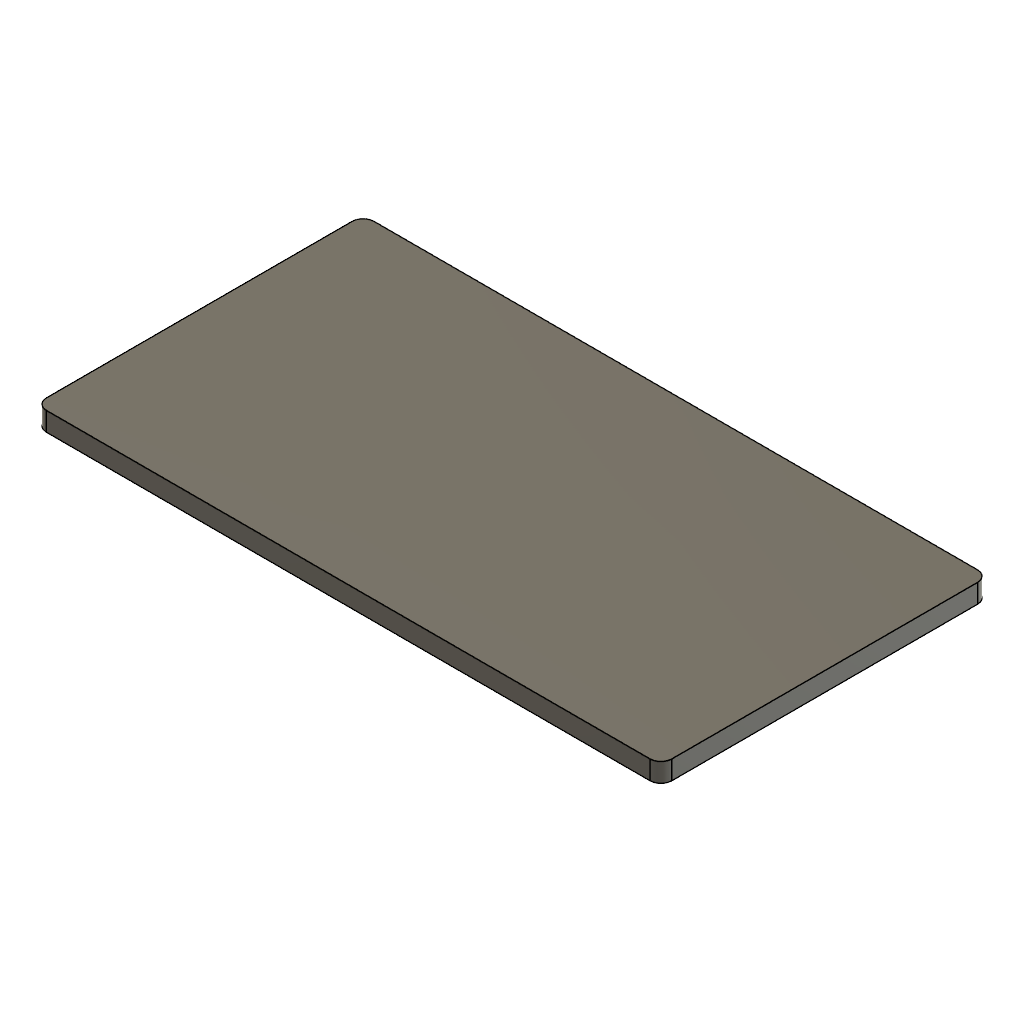
tapa_bateria (Autodesk Fusion 360 design; units mm, degrees)
part number: 2026-11-21-14-39-01-100
Autodesk Fusion 360 part; units mm, degrees
sketch "Sketch1" plane through (0, 0, 0) normal (0, 1, 0) x (1, 0, 0)
  line L0 (53.75, 26.25) -> (-53.75, 26.25)
  line L1 (-53.75, 26.25) -> (-53.75, -26.25)
  line L2 (-53.75, -26.25) -> (53.75, -26.25)
  line L3 (53.75, -26.25) -> (53.75, 26.25)
  line L4 (53.75, 26.25) -> (-53.75, -26.25) construction
  line L5 (-53.75, 26.25) -> (53.75, -26.25) construction
  line L6 (57.75, 30.25) -> (-57.75, 30.25)
  line L7 (-57.75, 30.25) -> (-57.75, -30.25)
  line L8 (-57.75, -30.25) -> (57.75, -30.25)
  line L9 (57.75, -30.25) -> (57.75, 30.25)
  dimension "d1" = 107.5
  dimension "d2" = 52.5
  dimension "d3" = 4
  constraint horizontal L0
  constraint perpendicular L0 L1
  constraint parallel L0 L2
  constraint parallel L1 L3
  constraint coincident L4 origin
  constraint coincident L5 origin
  measures "d1" distance of L1.end L2.end
  measures "d2" distance of L0.end L1.end
extrude "Extrude1" add sketch "Sketch1" along normal blind 30 contours L0 L1 L2 L3 | L6 L7 L8 L9 makes body 1
shell "Shell1" thickness 4 removed faces 1 at (-19.25, 30, 10.0833) on bodies 1
sketch "Sketch2" plane through (-57.75, 0, 0) normal (-1, 0, 0) x (0, 0, 1)
  line L0 (-30.25, 0) -> (30.25, 0)
  line L1 (30.25, 0) -> (30.25, 30)
  line L2 (30.25, 30) -> (-30.25, 30)
  line L3 (-30.25, 30) -> (-30.25, 0)
  line L4 (9, 17) -> (-9, 17)
  line L5 (-9, 17) -> (-9, 4)
  line L6 (-9, 4) -> (9, 4)
  line L7 (9, 4) -> (9, 17)
  line L8 (9, 17) -> (-9, 4) construction
  line L9 (-9, 17) -> (9, 4) construction
  point P0 (0, 10.5)
  dimension "d7" = 18
  dimension "d8" = 13
  dimension "d9" = 4
  constraint horizontal L4
  constraint perpendicular L4 L5
  constraint parallel L4 L6
  constraint parallel L5 L7
  constraint coincident L8 P0
  constraint coincident L9 P0
  measures "d7" distance of L5.end L6.end
  measures "d8" distance of L4.end L5.end
  measures "d9" distance of L0 L6
extrude "Extrude2" cut sketch "Sketch2" against normal blind 25 contours L4 L5 L6 L7 bodies 1
sketch "Sketch3" plane through (0, 0, 30.25) normal (0, 0, 1) x (1, 0, 0)
  line L0 (-57.75, 0) -> (57.75, 0)
  line L1 (57.75, 0) -> (57.75, 30)
  line L2 (57.75, 30) -> (-57.75, 30)
  line L3 (-57.75, 30) -> (-57.75, 0)
  line L4 (33.0622, 11) -> (50.0622, 11)
  line L5 (50.0622, 11) -> (50.0622, 4)
  line L6 (50.0622, 4) -> (33.0622, 4)
  line L7 (33.0622, 4) -> (33.0622, 11)
  dimension "d12" = 17
  dimension "d13" = 7
  dimension "d14" = 4
  constraint horizontal L4
  constraint vertical L5
  constraint horizontal L6
  constraint vertical L7
  measures "d12" distance of L4.start L4.end
  measures "d13" distance of L4.start L6.end
  measures "d14" distance of L0 L6
extrude "Extrude3" cut sketch "Sketch3" against normal blind 3 contours L4 L5 L6 L7 bodies 1
extrude "Extrude4" cut 1 faces at (44.3955, 6.3333, 27.25) along direction (0, 0, -1) blind 2 on bodies 1 bodies 1
sketch "Sketch4" plane through (0, 30, 0) normal (0, 1, 0) x (-1, 0, 0)
  line L0 (-53.75, 26.25) -> (53.75, 26.25)
  line L1 (53.75, 26.25) -> (53.75, -26.25)
  line L2 (53.75, -26.25) -> (-53.75, -26.25)
  line L3 (-53.75, -26.25) -> (-53.75, 26.25)
  line L4 (-57.75, 30.25) -> (-57.75, -30.25)
  line L5 (-57.75, -30.25) -> (57.75, -30.25)
  line L6 (57.75, -30.25) -> (57.75, 30.25)
  line L7 (57.75, 30.25) -> (-57.75, 30.25)
  line L8 (57.75, -30.25) -> (-57.75, -30.25)
  line L9 (-57.75, -30.25) -> (-57.75, 30.25)
  line L10 (-57.75, 30.25) -> (57.75, 30.25)
  line L11 (57.75, 30.25) -> (57.75, -30.25)
  constraint horizontal L8
  constraint vertical L9
  constraint horizontal L10
  constraint vertical L11
  constraint coincident L4.start L7.end
  constraint coincident L5.end L6.start
extrude "Extrude5" add sketch "Sketch4" along normal blind 2 bodies 1
sketch "Sketch5" plane through (0, 32, 0) normal (0, 1, 0) x (-1, 0, 0)
  line L0 (53.75, -26.25) -> (-53.75, -26.25)
  line L1 (-53.75, -26.25) -> (-53.75, 26.25)
  line L2 (-53.75, 26.25) -> (53.75, 26.25)
  line L3 (53.75, 26.25) -> (53.75, -26.25)
  line L4 (57.75, 30.25) -> (-57.75, 30.25)
  line L5 (-57.75, 30.25) -> (-57.75, -30.25)
  line L6 (-57.75, -30.25) -> (57.75, -30.25)
  line L7 (57.75, -30.25) -> (57.75, 30.25)
  line L8 (57.75, -30.25) -> (-57.75, -30.25)
  line L9 (-57.75, -30.25) -> (-57.75, 30.25)
  line L10 (-57.75, 30.25) -> (57.75, 30.25)
  line L11 (57.75, 30.25) -> (57.75, -30.25)
  constraint horizontal L8
  constraint vertical L9
  constraint horizontal L10
  constraint vertical L11
  constraint coincident L4.end L5.start
  constraint coincident L6.end L7.start
extrude "Extrude6" add sketch "Sketch5" along normal blind 3.5 separate body contours L0 L1 L2 L3 | L4 L5 L6 L7 L8 L9 L10 L11 makes body 2
sketch "Sketch6" plane through (0, 32, 0) normal (0, -1, 0) x (1, 0, 0)
  line L0 (57.75, 30.25) -> (-57.75, 30.25)
  line L1 (-57.75, 30.25) -> (-57.75, -30.25)
  line L2 (-57.75, -30.25) -> (57.75, -30.25)
  line L3 (57.75, -30.25) -> (57.75, 30.25)
  line L4 (-53.5, -26) -> (53.5, -26)
  line L5 (53.5, -26) -> (53.5, 26)
  line L6 (53.5, 26) -> (-53.5, 26)
  line L7 (-53.5, 26) -> (-53.5, -26)
  dimension "d23" = -4.25
extrude "Extrude7" add sketch "Sketch6" along normal blind 3.5 contours L4 L5 L6 L7 bodies 2
fillet "Fillet1" radius 2 8 edges at (57.75, 16, 30.25) (-57.75, 16, 30.25) (57.75, 16, -30.25) (-57.75, 16, -30.25) (57.75, 33.75, 30.25) (-57.75, 33.75, 30.25) (57.75, 33.75, -30.25) (-57.75, 33.75, -30.25) on bodies 1 2
fillet "Fillet2" radius 1 4 edges at (-55.75, 17, -9) (-55.75, 4, 9) (-55.75, 4, -9) (-55.75, 17, 9) on bodies 1
fillet "Fillet3" radius 0.5 4 edges at (50.0622, 11, 28.25) (50.0622, 4, 28.25) (33.0622, 4, 28.25) (33.0622, 11, 28.25) on bodies 1
sketch "Sketch7" plane through (0, 0, 30.25) normal (0, 0, 1) x (1, 0, 0)
  line L0 (50.0622, 10.5) -> (50.0622, 4.5)
  arc A0 (49.5622, 4) -> (50.0622, 4.5) centre (49.5622, 4.5) ccw
  line L1 (49.5622, 4) -> (33.5622, 4)
  arc A1 (33.0622, 4.5) -> (33.5622, 4) centre (33.5622, 4.5) ccw
  line L2 (33.0622, 4.5) -> (33.0622, 10.5)
  arc A2 (33.5622, 11) -> (33.0622, 10.5) centre (33.5622, 10.5) ccw
  line L3 (33.5622, 11) -> (49.5622, 11)
  arc A3 (50.0622, 10.5) -> (49.5622, 11) centre (49.5622, 10.5) ccw
  line L4 (-55.75, 32) -> (-55.75, 0)
  line L5 (-55.75, 0) -> (55.75, 0)
  line L6 (55.75, 0) -> (55.75, 32)
  line L7 (55.75, 32) -> (-55.75, 32)
  line L8 (-29.8148, 17) -> (-13.8148, 17)
  line L9 (-13.8148, 17) -> (-13.8148, 4)
  line L10 (-13.8148, 4) -> (-29.8148, 4)
  line L11 (-29.8148, 4) -> (-29.8148, 17)
  dimension "d32" = 16
  dimension "d33" = 13
  dimension "d34" = 4
  constraint horizontal L8
  constraint vertical L9
  constraint horizontal L10
  constraint vertical L11
  measures "d32" distance of L8.start L8.end
  measures "d33" distance of L8.start L10.end
  measures "d34" distance of L5 L10
extrude "Extrude8" cut sketch "Sketch7" against normal blind 4 contours L8 L9 L10 L11 bodies 1
hidden bodies 1
